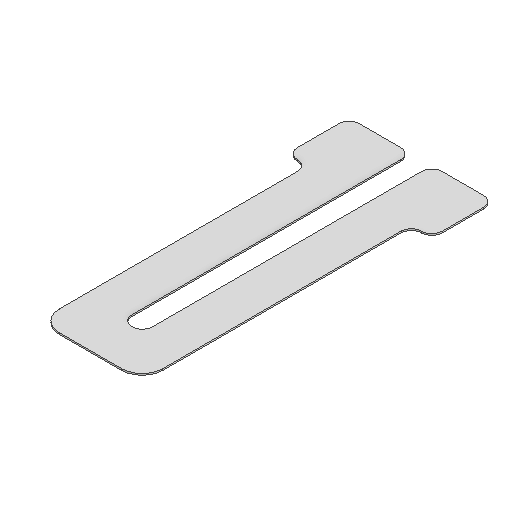
# Autodesk Inventor part: CortoBottoni
Saved by Autodesk Inventor 2025.4 (Build 294407000, 407)
## iProperties
Created: 2026-10-09
Part Number: CortoBottoni
Material: Generic
Document SubType Name: Modeling
Designer: gdira
Density: 1 g/cm^3
Appearance: Default
Author: gdira
Autodesk Inventor part; units mm, degrees
ref_plane "YZ Plane" through (0, 0, 0) normal (1, 0, 0) x (0, 1, 0)
ref_plane "XZ Plane" through (0, 0, 0) normal (0, 1, 0) x (-1, 0, 0)
ref_plane "XY Plane" through (0, 0, 0) normal (0, 0, 1) x (1, 0, 0)
sketch "Sketch1" plane through (0, 0, 0) normal (0, 1, 0) x (-1, 0, 0)
  line L0 (-0.5531, 77.0277) -> (-0.5531, 42.0131)
  line L1 (1.4469, 53.0262) -> (1.4469, 77.0277)
  line L2 (-4.5531, 80.0277) -> (-4.5531, 60.0209)
  line L3 (-2.5531, 82.0277) -> (3.4469, 82.0277)
  line L4 (5.4469, 80.0277) -> (5.4469, 60.0487)
  arc A0 (-2.5531, 82.0277) -> (-4.5531, 80.0277) centre (-2.5531, 80.0277) ccw
  arc A1 (5.4469, 80.0277) -> (3.4469, 82.0277) centre (3.4469, 80.0277) ccw
  line L5 (5.4469, 57.0305) -> (5.4469, 63.6029)
  line L6 (-9.5532, 56.0131) -> (-5.5531, 56.0131)
  line L7 (-4.5531, 57.0131) -> (-4.5531, 60.0209)
  arc A2 (-5.5531, 56.0131) -> (-4.5531, 57.0131) centre (-5.5531, 57.0131) ccw
  arc A3 (5.4469, 57.0305) -> (6.4469, 56.0305) centre (6.4469, 57.0305) ccw
  arc A4 (0.4469, 78.0277) -> (-0.5531, 77.0277) centre (0.4469, 77.0277) ccw
  arc A5 (1.4469, 77.0277) -> (0.4469, 78.0277) centre (0.4469, 77.0277) ccw
  line L8 (1.4469, 53.0296) -> (1.4469, 53.4269)
  line L9 (1.4469, 53.4269) -> (1.4469, 47.0305)
  line L10 (1.4469, 51.0305) -> (1.4469, 56.0305)
  line L11 (-0.5531, 56.0305) -> (-5.5531, 56.0305)
  line L12 (-6.5531, 55.0305) -> (-6.5531, 51.0305)
  line L13 (-5.5531, 50.0305) -> (-1.5531, 50.0305)
  line L14 (-0.5531, 51.0305) -> (-0.5531, 56.0305)
  arc A6 (1.4469, 47.0305) -> (2.4469, 46.0305) centre (2.4469, 47.0305) ccw
  arc A7 (-1.5531, 50.0305) -> (-0.5531, 51.0305) centre (-1.5531, 51.0305) ccw
  arc A8 (-6.5531, 51.0305) -> (-5.5531, 50.0305) centre (-5.5531, 51.0305) ccw
  arc A9 (-5.5531, 56.0305) -> (-6.5531, 55.0305) centre (-5.5531, 55.0305) ccw
  line L15 (-32.2568, 112.8346) -> (-32.2568, 77.8199)
  line L16 (-30.2568, 88.8331) -> (-30.2568, 112.8346)
  line L17 (-36.2568, 115.8346) -> (-36.2568, 95.8277)
  line L18 (-34.2568, 117.8346) -> (-28.2568, 117.8346)
  line L19 (-26.2568, 115.8346) -> (-26.2568, 95.8556)
  arc A10 (-34.2568, 117.8346) -> (-36.2568, 115.8346) centre (-34.2568, 115.8346) ccw
  arc A11 (-26.2568, 115.8346) -> (-28.2568, 117.8346) centre (-28.2568, 115.8346) ccw
  line L20 (-21.2569, 91.8374) -> (-25.2568, 91.8374)
  line L21 (-26.2568, 92.8374) -> (-26.2568, 99.4097)
  line L22 (-41.2568, 91.8199) -> (-37.2568, 91.8199)
  line L23 (-36.2568, 92.8199) -> (-36.2568, 95.8277)
  arc A12 (-37.2568, 91.8199) -> (-36.2568, 92.8199) centre (-37.2568, 92.8199) ccw
  arc A13 (-26.2568, 92.8374) -> (-25.2568, 91.8374) centre (-25.2568, 92.8374) ccw
  arc A14 (-31.2568, 113.8346) -> (-32.2568, 112.8346) centre (-31.2568, 112.8346) ccw
  arc A15 (-30.2568, 112.8346) -> (-31.2568, 113.8346) centre (-31.2568, 112.8346) ccw
  line L24 (-30.2568, 88.8364) -> (-30.2568, 89.2337)
  line L25 (-30.2568, 89.2337) -> (-30.2568, 87.8374)
  line L26 (-30.2568, 91.8374) -> (-21.2568, 91.8374)
  line L27 (-20.2568, 90.8374) -> (-20.2568, 87.8374)
  line L28 (-21.2568, 86.8374) -> (-29.2568, 86.8374)
  line L29 (-30.2568, 86.8374) -> (-30.2568, 91.8374)
  line L30 (-32.2568, 91.8374) -> (-41.2568, 91.8374)
  line L31 (-42.2568, 90.8374) -> (-42.2568, 87.8374)
  line L32 (-41.2568, 86.8374) -> (-33.2568, 86.8374)
  line L33 (-32.2568, 87.8374) -> (-32.2568, 91.8374)
  arc A16 (-20.2568, 90.8374) -> (-21.2568, 91.8374) centre (-21.2568, 90.8374) ccw
  arc A17 (-21.2568, 86.8374) -> (-20.2568, 87.8374) centre (-21.2568, 87.8374) ccw
  arc A18 (-30.2568, 87.8374) -> (-29.2568, 86.8374) centre (-29.2568, 87.8374) ccw
  arc A19 (-33.2568, 86.8374) -> (-32.2568, 87.8374) centre (-33.2568, 87.8374) ccw
  arc A20 (-42.2568, 87.8374) -> (-41.2568, 86.8374) centre (-41.2568, 87.8374) ccw
  arc A21 (-41.2568, 91.8374) -> (-42.2568, 90.8374) centre (-41.2568, 90.8374) ccw
  line L34 (1.4469, 56.0305) -> (1.4469, 50.0305)
  line L35 (2.4469, 50.0305) -> (6.4469, 50.0305)
  line L36 (7.4469, 51.0305) -> (7.4469, 55.0305)
  line L37 (6.4469, 56.0305) -> (1.4469, 56.0305)
  arc A22 (7.4469, 55.0305) -> (6.4469, 56.0305) centre (6.4469, 55.0305) ccw
  arc A23 (6.4469, 50.0305) -> (7.4469, 51.0305) centre (6.4469, 51.0305) ccw
  arc A24 (1.4469, 51.0305) -> (2.4469, 50.0305) centre (2.4469, 51.0305) ccw
  point P0 (0.1272, 61.4459)
  point P1 (0.4469, 78.0277)
  point P2 (11.4469, 56.0305)
  point P3 (-6.5531, 50.0305)
  point P4 (-6.5531, 56.0305)
  point P5 (-0.5531, 50.0305)
  point P6 (-5.3673, 56.0305)
  point P7 (-0.5531, 51.0305)
  point P8 (0.4469, 78.0277)
  point P9 (-31.5765, 97.2528)
  point P10 (-20.2568, 86.8374)
  point P11 (-20.2568, 91.8374)
  point P12 (-42.2568, 86.8374)
  point P13 (-42.2568, 91.8374)
  point P14 (-32.2568, 86.8374)
  point P15 (7.4469, 50.0305)
  point P16 (-5.7389, 56.0131)
  dimension "d1" = 4
  dimension "d2" = 2
  dimension "d5" = 2
  dimension "d7" = 1
  dimension "d8" = 1
  dimension "d23" = 6
  dimension "d24" = 6
  dimension "d31" = 4
  dimension "d32" = 4
  dimension "d33" = 2
  dimension "d34" = 2
  dimension "d35" = 1
  dimension "d36" = 1
  dimension "d37" = 10
  dimension "d38" = 5
  dimension "d39" = 10
  dimension "d40" = 5
  dimension "d41" = 1
  dimension "d45" = 6
  dimension "d46" = 6
  dimension "d47" = 1
  constraints: 76 end point, 50 point on circle, 44 tangent, 30 point on line, 25 centre point, 12 equal radius, 10 parallel, 6 vertical, 5 horizontal, 5 perpendicular, 2 collinear, 12 other
  measures "d1" distance between parallel lines of L2 L0
  measures "d2" distance between parallel lines of L0 L1
  measures "d5" radius of A0
  measures "d7" radius of A2
  measures "d8" radius of A4
  measures "d23" distance of point (-0.553, 50.03) point (-6.553, 50.03)
  measures "d24" distance of point (-6.553, 50.03) point (-6.553, 56.03)
  measures "d31" distance between parallel lines of L16 L19
  measures "d32" distance between parallel lines of L17 L15
  measures "d33" distance between parallel lines of L15 L16
  measures "d34" radius of A10
  measures "d35" radius of A12
  measures "d36" radius of A14
  measures "d37" distance of point (-20.257, 86.837) L29.start
  measures "d38" distance of point (-20.257, 91.837) point (-20.257, 86.837)
  measures "d39" distance of point (-32.257, 86.837) point (-42.257, 86.837)
  measures "d40" distance of point (-42.257, 86.837) point (-42.257, 91.837)
  measures "d41" radius of A16
  measures "d45" distance of L10.end L34.end
  measures "d46" distance of point (7.447, 50.03) L34.end
  measures "d47" radius of A22
extrude "Extrusion1" add sketch "Sketch1" along normal blind 0.15 contours L0 L11 A2 L7 L2 A0 L3 A1 L4 L5 A3 L37 L1 A5 A4 | L0 A7 L13 A8 L12 A9 L6 A2 L11 | A2 L6 A9 L11 | L37 A22 L36 A23 L35 A24 L9 L1
body "Solid1"
